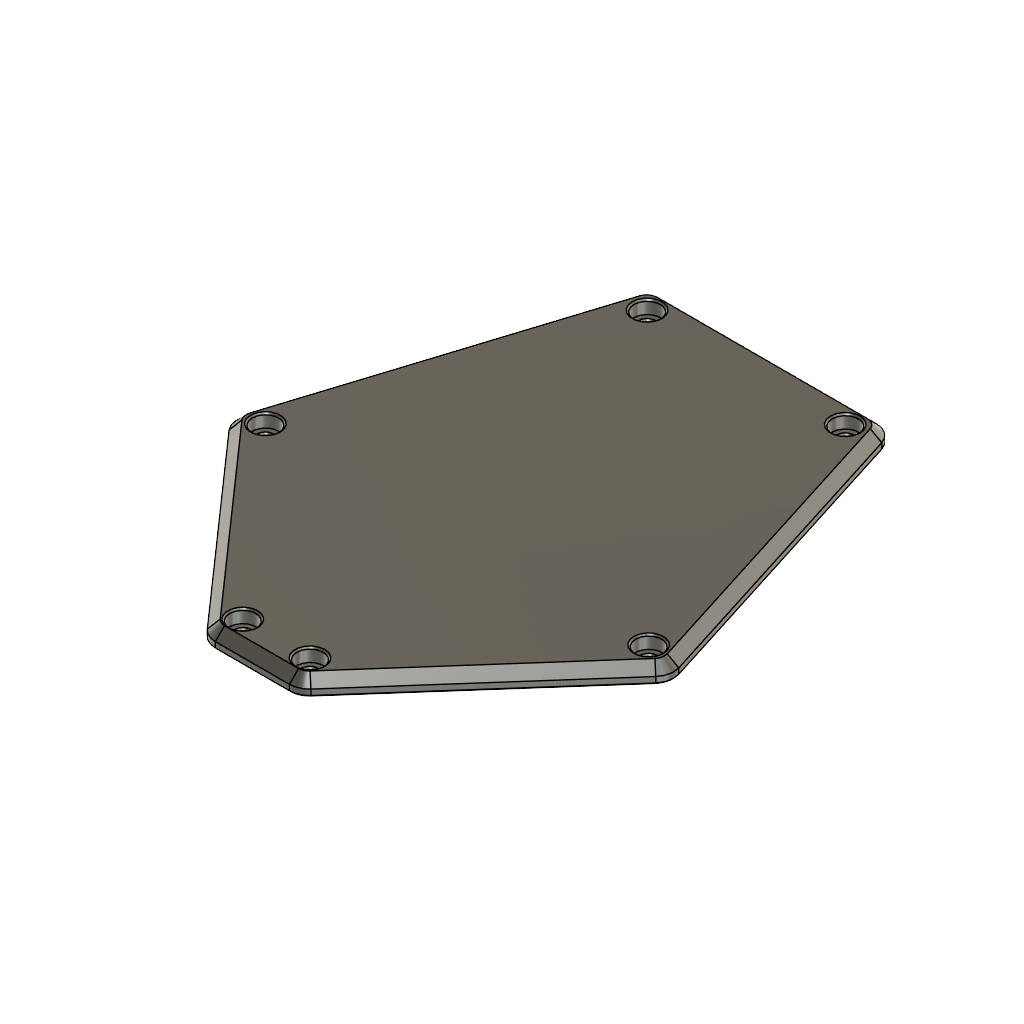
Glitched 38 centerpiece (Autodesk Fusion 360 design; units mm, degrees)
Autodesk Fusion 360 part; units mm, degrees
sketch "Sketch1" plane through (0, 0, 0) normal (0, 0, 1) x (1, 0, 0)
sketch "center_piece" plane through (0, 0, 0) normal (0, 0, 1) x (1, 0, 0)
  line L0 (151.8706, -146.3743) -> (166.111, -101.2095)
  line L1 (168.9721, -99.1116) -> (201.0068, -99.1116)
  line L2 (203.8679, -101.2095) -> (218.1083, -146.3743)
  line L3 (217.4977, -149.2602) -> (192.8843, -177.184)
  line L4 (190.6338, -178.2003) -> (179.3451, -178.2003)
  line L5 (177.0946, -177.184) -> (152.4812, -149.2602)
  arc A0 (168.9721, -99.1116) -> (166.111, -101.2095) centre (168.9721, -102.1116) ccw
  arc A1 (203.8679, -101.2095) -> (201.0068, -99.1116) centre (201.0068, -102.1116) ccw
  arc A2 (217.4977, -149.2602) -> (218.1083, -146.3743) centre (215.2472, -147.2765) ccw
  arc A3 (190.6338, -178.2003) -> (192.8843, -177.184) centre (190.6338, -175.2003) ccw
  arc A4 (177.0946, -177.184) -> (179.3451, -178.2003) centre (179.3451, -175.2003) ccw
  arc A5 (151.8706, -146.3743) -> (152.4812, -149.2602) centre (154.7317, -147.2765) ccw
  circle A6 centre (169.8966, -102.9801) radius 1.025
  circle A7 centre (155.7982, -147.0294) radius 1.025
  circle A8 centre (179.8718, -174.5508) radius 1.025
  circle A9 centre (200.0823, -102.9801) radius 1.025
  circle A10 centre (214.1807, -147.0294) radius 1.025
  circle A11 centre (190.1071, -174.5508) radius 1.025
extrude "Extrude1" add sketch "center_piece" along normal blind 2.5
sketch "Sketch4" plane through (0, 0, 2.5) normal (0, 0, 1) x (-1, 0, 0)
  circle A0 centre (-155.7982, 147.0294) radius 1.025
  circle A1 centre (-214.1807, 147.0294) radius 1.025
  circle A2 centre (-190.1071, 174.5508) radius 1.025
  circle A3 centre (-200.0823, 102.9801) radius 1.025
  circle A4 centre (-179.8718, 174.5508) radius 1.025
  circle A5 centre (-169.8966, 102.9801) radius 1.025
  arc A6 (-168.9721, 99.1116) -> (-166.111, 101.2095) centre (-168.9721, 102.1116) ccw
  line L0 (-166.111, 101.2095) -> (-151.8706, 146.3743)
  arc A7 (-151.8706, 146.3743) -> (-152.4812, 149.2602) centre (-154.7317, 147.2765) ccw
  line L1 (-152.4812, 149.2602) -> (-177.0946, 177.184)
  arc A8 (-177.0946, 177.184) -> (-179.3451, 178.2003) centre (-179.3451, 175.2003) ccw
  line L2 (-179.3451, 178.2003) -> (-190.6338, 178.2003)
  arc A9 (-190.6338, 178.2003) -> (-192.8843, 177.184) centre (-190.6338, 175.2003) ccw
  line L3 (-192.8843, 177.184) -> (-217.4977, 149.2602)
  arc A10 (-217.4977, 149.2602) -> (-218.1083, 146.3743) centre (-215.2472, 147.2765) ccw
  line L4 (-218.1083, 146.3743) -> (-203.8679, 101.2095)
  arc A11 (-203.8679, 101.2095) -> (-201.0068, 99.1116) centre (-201.0068, 102.1116) ccw
  line L5 (-201.0068, 99.1116) -> (-168.9721, 99.1116)
  line L6 (-154.7317, 147.2765) -> (-179.3451, 175.2003)
  line L7 (-179.3451, 175.2003) -> (-190.6338, 175.2003)
  line L8 (-190.6338, 175.2003) -> (-215.2472, 147.2765)
  line L9 (-215.2472, 147.2765) -> (-201.0068, 102.1116)
  line L10 (-201.0068, 102.1116) -> (-168.9721, 102.1116)
  line L11 (-168.9721, 102.1116) -> (-154.7317, 147.2765)
  line L12 (-155.8552, 147.0387) -> (-179.7967, 174.2003)
  line L13 (-179.7967, 174.2003) -> (-190.1822, 174.2003)
  line L14 (-190.1822, 174.2003) -> (-214.1237, 147.0387)
  line L15 (-214.1237, 147.0387) -> (-200.2735, 103.1116)
  line L16 (-200.2735, 103.1116) -> (-169.7054, 103.1116)
  line L17 (-169.7054, 103.1116) -> (-155.8552, 147.0387)
  line L18 (-159.2256, 146.3256) -> (-181.1514, 171.2003)
  line L19 (-181.1514, 171.2003) -> (-188.8275, 171.2003)
  line L20 (-188.8275, 171.2003) -> (-210.7532, 146.3256)
  line L21 (-210.7532, 146.3256) -> (-198.0738, 106.1116)
  line L22 (-198.0738, 106.1116) -> (-171.9051, 106.1116)
  line L23 (-171.9051, 106.1116) -> (-159.2256, 146.3256)
  line L24 (-160.3491, 146.0878) -> (-181.603, 170.2003)
  line L25 (-181.603, 170.2003) -> (-188.3759, 170.2003)
  line L26 (-188.3759, 170.2003) -> (-209.6298, 146.0878)
  line L27 (-209.6298, 146.0878) -> (-197.3406, 107.1116)
  line L28 (-197.3406, 107.1116) -> (-172.6383, 107.1116)
  line L29 (-172.6383, 107.1116) -> (-160.3491, 146.0878)
  line L30 (-163.7196, 145.3747) -> (-182.9577, 167.2003)
  line L31 (-182.9577, 167.2003) -> (-187.0212, 167.2003)
  line L32 (-187.0212, 167.2003) -> (-206.2593, 145.3747)
  line L33 (-206.2593, 145.3747) -> (-195.1409, 110.1116)
  line L34 (-195.1409, 110.1116) -> (-174.838, 110.1116)
  line L35 (-174.838, 110.1116) -> (-163.7196, 145.3747)
  line L36 (-164.8431, 145.137) -> (-183.4093, 166.2003)
  line L37 (-183.4093, 166.2003) -> (-186.5696, 166.2003)
  line L38 (-186.5696, 166.2003) -> (-205.1358, 145.137)
  line L39 (-205.1358, 145.137) -> (-194.4077, 111.1116)
  line L40 (-194.4077, 111.1116) -> (-175.5712, 111.1116)
  line L41 (-175.5712, 111.1116) -> (-164.8431, 145.137)
  line L42 (-168.2135, 144.4238) -> (-184.764, 163.2003)
  line L43 (-184.764, 163.2003) -> (-185.2149, 163.2003)
  line L44 (-185.2149, 163.2003) -> (-201.7654, 144.4238)
  line L45 (-201.7654, 144.4238) -> (-192.208, 114.1116)
  line L46 (-192.208, 114.1116) -> (-177.7709, 114.1116)
  line L47 (-177.7709, 114.1116) -> (-168.2135, 144.4238)
  line L48 (-169.337, 144.1861) -> (-184.9894, 161.9437)
  line L49 (-184.9894, 161.9437) -> (-200.6419, 144.1861)
  line L50 (-200.6419, 144.1861) -> (-191.4748, 115.1116)
  line L51 (-191.4748, 115.1116) -> (-178.5041, 115.1116)
  line L52 (-178.5041, 115.1116) -> (-169.337, 144.1861)
  line L53 (-172.7074, 143.4729) -> (-184.9894, 157.4068)
  line L54 (-184.9894, 157.4068) -> (-197.2715, 143.4729)
  line L55 (-197.2715, 143.4729) -> (-189.2751, 118.1116)
  line L56 (-189.2751, 118.1116) -> (-180.7038, 118.1116)
  line L57 (-180.7038, 118.1116) -> (-172.7074, 143.4729)
  line L58 (-173.8309, 143.2352) -> (-184.9894, 155.8945)
  line L59 (-184.9894, 155.8945) -> (-196.148, 143.2352)
  line L60 (-196.148, 143.2352) -> (-188.5418, 119.1116)
  line L61 (-188.5418, 119.1116) -> (-181.437, 119.1116)
  line L62 (-181.437, 119.1116) -> (-173.8309, 143.2352)
  line L63 (-177.2014, 142.522) -> (-184.9894, 151.3576)
  line L64 (-184.9894, 151.3576) -> (-192.7775, 142.522)
  line L65 (-192.7775, 142.522) -> (-186.3422, 122.1116)
  line L66 (-186.3422, 122.1116) -> (-183.6367, 122.1116)
  line L67 (-183.6367, 122.1116) -> (-177.2014, 142.522)
  line L68 (-184.37, 123.1116) -> (-178.3249, 142.2843)
  line L69 (-178.3249, 142.2843) -> (-184.9894, 149.8452)
  line L70 (-184.9894, 149.8452) -> (-191.654, 142.2843)
  line L71 (-191.654, 142.2843) -> (-185.6089, 123.1116)
  line L72 (-185.6089, 123.1116) -> (-184.37, 123.1116)
  line L73 (-184.9894, 145.3083) -> (-188.2836, 141.5711)
  line L74 (-188.2836, 141.5711) -> (-184.9894, 131.1234)
  line L75 (-184.9894, 131.1234) -> (-181.6953, 141.5711)
  line L76 (-181.6953, 141.5711) -> (-184.9894, 145.3083)
  line L77 (-184.9894, 143.796) -> (-187.1601, 141.3334)
  line L78 (-187.1601, 141.3334) -> (-184.9894, 134.4489)
  line L79 (-184.9894, 134.4489) -> (-182.8188, 141.3334)
  line L80 (-182.8188, 141.3334) -> (-184.9894, 143.796)
  circle A12 centre (-155.7982, 147.0294) radius 2.025
  circle A13 centre (-169.8966, 102.9801) radius 2.025
  circle A14 centre (-200.0823, 102.9801) radius 2.025
  circle A15 centre (-214.1807, 147.0294) radius 2.025
  circle A16 centre (-190.1071, 174.5508) radius 2.025
  circle A17 centre (-179.8718, 174.5508) radius 2.025
  dimension "d9" = -3
  dimension "d10" = -1
  dimension "d11" = -3
  dimension "d12" = -1
  dimension "d13" = -3
  dimension "d14" = -1
  dimension "d15" = -3
  dimension "d16" = -1
  dimension "d17" = -3
  dimension "d18" = -1
  dimension "d19" = -3
  dimension "d20" = -1
  dimension "d21" = -3
  dimension "d22" = -1
  dimension "d23" = 1
  dimension "d24" = 1
  dimension "d25" = 1
  dimension "d26" = 1
  dimension "d27" = 1
  dimension "d28" = 1
sketch "Sketch5" plane through (0, 0, 2.5) normal (0, 0, 1) x (-1, 0, 0)
  circle A0 centre (-155.7982, 147.0294) radius 1.025
  circle A1 centre (-214.1807, 147.0294) radius 1.025
  circle A2 centre (-190.1071, 174.5508) radius 1.025
  circle A3 centre (-200.0823, 102.9801) radius 1.025
  circle A4 centre (-179.8718, 174.5508) radius 1.025
  circle A5 centre (-169.8966, 102.9801) radius 1.025
  arc A6 (-168.9721, 99.1116) -> (-166.111, 101.2095) centre (-168.9721, 102.1116) ccw
  line L0 (-166.111, 101.2095) -> (-151.8706, 146.3743)
  arc A7 (-151.8706, 146.3743) -> (-152.4812, 149.2602) centre (-154.7317, 147.2765) ccw
  line L1 (-152.4812, 149.2602) -> (-177.0946, 177.184)
  arc A8 (-177.0946, 177.184) -> (-179.3451, 178.2003) centre (-179.3451, 175.2003) ccw
  line L2 (-179.3451, 178.2003) -> (-190.6338, 178.2003)
  arc A9 (-190.6338, 178.2003) -> (-192.8843, 177.184) centre (-190.6338, 175.2003) ccw
  line L3 (-192.8843, 177.184) -> (-217.4977, 149.2602)
  arc A10 (-217.4977, 149.2602) -> (-218.1083, 146.3743) centre (-215.2472, 147.2765) ccw
  line L4 (-218.1083, 146.3743) -> (-203.8679, 101.2095)
  arc A11 (-203.8679, 101.2095) -> (-201.0068, 99.1116) centre (-201.0068, 102.1116) ccw
  line L5 (-201.0068, 99.1116) -> (-168.9721, 99.1116)
  circle A12 centre (-169.8966, 102.9801) radius 2
  circle A13 centre (-200.0823, 102.9801) radius 2
  circle A14 centre (-214.1807, 147.0294) radius 2
  circle A15 centre (-190.1071, 174.5508) radius 2
  circle A16 centre (-179.8718, 174.5508) radius 2
  circle A17 centre (-155.7982, 147.0294) radius 2
  dimension "d31" = 4
  dimension "d32" = 4
  dimension "d33" = 4
  dimension "d34" = 4
  dimension "d35" = 4
  dimension "d36" = 4
  constraint concentric A5 A12
  constraint concentric A3 A13
  constraint concentric A1 A14
  constraint concentric A2 A15
  constraint concentric A4 A16
  constraint concentric A0 A17
  measures "d31" diameter of A12
  measures "d32" diameter of A13
  measures "d33" diameter of A14
  measures "d34" diameter of A15
  measures "d35" diameter of A16
  measures "d36" diameter of A17
extrude "Extrude3" cut sketch "Sketch5" against normal blind 2 contours A12 | A13 | A14 | A15 | A16 | A17
chamfer "Chamfer1" distance 0.25 angle 45 12 edges at (168.941, -103.3508, 0.5) (171.7613, -103.7034, 2.5) (199.1266, -103.3508, 0.5) (201.9469, -103.7034, 2.5) (216.0453, -147.7526, 2.5) (213.225, -147.4001, 0.5) (189.1515, -174.9214, 0.5) (191.9718, -175.274, 2.5) (178.9161, -174.9214, 0.5) (181.7364, -175.274, 2.5) (157.6629, -147.7526, 2.5) (154.8426, -147.4001, 0.5) 1 faces at (189.8896, -132.4005, 0) tangent chain off
chamfer "Chamfer2" distance 1.4 angle 45 12 edges at (184.9894, -99.1116, 2.5) (167.1982, -99.6923, 2.5) (158.9908, -123.7919, 2.5) (151.7967, -147.8975, 2.5) (164.7879, -163.2221, 2.5) (178.1104, -177.9344, 2.5) (184.9894, -178.2003, 2.5) (191.8685, -177.9344, 2.5) (205.191, -163.2221, 2.5) (218.1822, -147.8975, 2.5) (210.9881, -123.7919, 2.5) (202.7807, -99.6923, 2.5) tangent chain off
